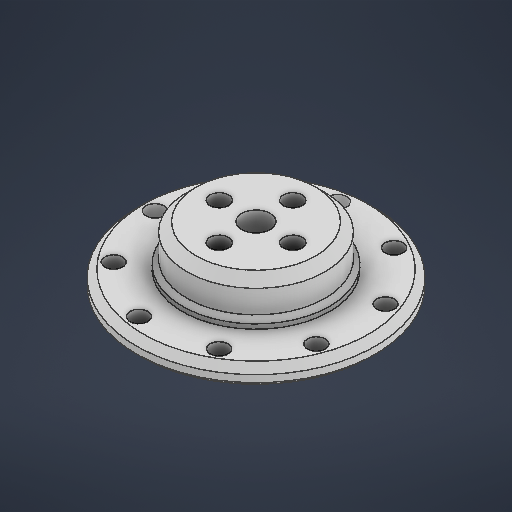
# Autodesk Inventor part: roter_v2
Saved by Autodesk Inventor 2026.2 (Build 302298010, 298A)
## iProperties
Created: 2026-04-11
Part Number: roter_v2
Material: 일반
Document SubType Name: Modeling
Designer: work
Density: 1 g/cm^3
Appearance: 기본값
Author: work
Autodesk Inventor part; units mm, degrees
ref_plane "YZ Plane" through (0, 0, 0) normal (1, 0, 0) x (0, 1, 0)
ref_plane "XZ Plane" through (0, 0, 0) normal (0, 1, 0) x (-1, 0, 0)
ref_plane "XY Plane" through (0, 0, 0) normal (0, 0, 1) x (1, 0, 0)
sketch "스케치1" plane through (0, 0, 0) normal (0, 1, 0) x (-1, 0, 0)
  circle A0 centre (0, 0) radius 22 construction
  line L0 (0, 0) -> (22, 0) construction
  circle A1 centre (22, 0) radius 1.95
  line L1 (0, 0) -> (16.853, 14.1413) construction
  circle A2 centre (16.853, 14.1413) radius 1.95
  line L2 (0, 0) -> (3.8203, 21.6658) construction
  circle A3 centre (3.8203, 21.6658) radius 1.95
  line L3 (0, 0) -> (-11, 19.0526) construction
  circle A4 centre (-11, 19.0526) radius 1.95
  line L4 (0, 0) -> (-20.6732, 7.5244) construction
  circle A5 centre (-20.6732, 7.5244) radius 1.95
  line L5 (0, 0) -> (-20.6732, -7.5244) construction
  circle A6 centre (-20.6732, -7.5244) radius 1.95
  line L6 (0, 0) -> (-11, -19.0526) construction
  circle A7 centre (-11, -19.0526) radius 1.95
  line L7 (0, 0) -> (3.8203, -21.6658) construction
  circle A8 centre (3.8203, -21.6658) radius 1.95
  line L8 (0, 0) -> (16.853, -14.1413) construction
  circle A9 centre (16.853, -14.1413) radius 1.95
  circle A10 centre (0, 0) radius 26
  circle A11 centre (0, 0) radius 12.5
  dimension "d0" = 3.9
  dimension "d1" = 22
  dimension "d4" = 360
  dimension "d6" = 4
  dimension "d7" = 25
  constraints: 18 end point, 14 coincident, 11 centre point, 1 horizontal, 1 horizontal alignment, 46 other
  measures "d0" diameter of A1
  measures "d1" distance of L0.start L0.end
  measures "d7" diameter of A11
extrude "돌출1" add sketch "스케치1" along normal blind 4
sketch "스케치2" plane through (0, 4, 0) normal (0, 1, 0) x (1, 0, 0)
  point P0 (0, 0)
sketch "스케치3" plane through (0, 4, 0) normal (0, 1, 0) x (1, 0, 0)
  circle A0 centre (0, 0) radius 15
  dimension "d10" = 30
  constraints: 1 centre point, 1 coincident
  measures "d10" diameter of A0
extrude "돌출2" add sketch "스케치3" along normal blind 9
sketch "스케치4" plane through (0, 4, 0) normal (0, 1, 0) x (1, 0, 0)
  circle A0 centre (0, 0) radius 16
  circle A1 centre (0, 0) radius 15 projected
  dimension "d13" = 1
  constraints: 1 centre point, 1 coincident
  measures "d13" radial gap between concentric circles of A0 A1
extrude "돌출3" add sketch "스케치4" along normal blind 1
chamfer "모따기1" distance 1 angle 45 3 edges at (-15, 5, 0) (12.5, 0, 0) (26, 0, 0)
sketch "스케치5" plane through (0, 13, 0) normal (0, 1, 0) x (1, 0, 0)
  circle A0 centre (0, 0) radius 8 construction
  line L0 (0, 0) -> (8, 0) construction
  circle A1 centre (8, 0) radius 2.05
  circle A2 centre (0, 8) radius 2.05
  circle A3 centre (-8, 0) radius 2.05
  circle A4 centre (0, -8) radius 2.05
  circle A5 centre (0, 0) radius 3.1
  dimension "d19" = 16
  dimension "d20" = 4.1
  dimension "d23" = 360
  dimension "d25" = 6.2
  constraints: 5 centre point, 3 coincident, 2 end point, 1 horizontal, 1 horizontal alignment, 11 other
  measures "d20" diameter of A1
  measures "d25" diameter of A5
extrude "돌출4" cut sketch "스케치5" against normal through all
chamfer "모따기2" distance 2 angle 45 1 edges at (-15, 13, 0)
chamfer "모따기3" distance 1.5 angle 45 1 edges at (26, 4, 0)
